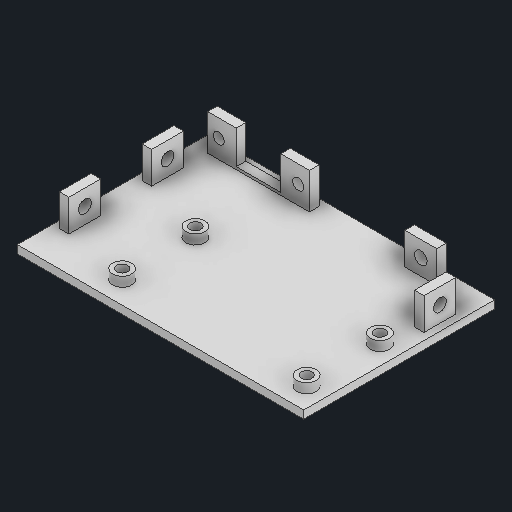
# Autodesk Inventor part: base_plate_compact
Saved by Autodesk Inventor 2027.1 (Build 311270010, 270A)
## iProperties
Created: 2026-10-29
Part Number: base_plate_compact
Material: Generic
Document SubType Name: Modeling
Designer: alexg
Density: 1 g/cm^3
Appearance: Default
Author: alexg
Autodesk Inventor part; units mm, degrees
ref_plane "Work Plane1" through (0, -31.66, 0) normal (0, 1, 0) x (-1, 0, 0)
sketch "Plate sketch" plane through (0, -31.66, 0) normal (0, 1, 0) x (-1, 0, 0)
  line L0 (45, -30) -> (-45, -30)
  line L1 (-45, -30) -> (-45, 30)
  line L2 (-45, 30) -> (45, 30)
  line L3 (45, 30) -> (45, -30)
  constraints: 8 end point, 2 parallel, 1 horizontal, 1 perpendicular
extrude "Plate" add sketch "Plate sketch" against normal blind 2.5
ref_plane "Work Plane2" through (0, -31.66, 0) normal (0, 1, 0) x (-1, 0, 0)
sketch "Pi standoffs sketch" plane through (0, -31.66, 0) normal (0, 1, 0) x (-1, 0, 0)
  circle A0 centre (-38.97, 0.03) radius 3
  circle A1 centre (19.03, 0.03) radius 3
  circle A2 centre (-38.97, 23.03) radius 3
  circle A3 centre (19.03, 23.03) radius 3
  constraints: 4 centre point
extrude "Pi standoffs" add sketch "Pi standoffs sketch" along normal blind 3
ref_plane "Work Plane3" through (0, -28.66, 0) normal (0, 1, 0) x (-1, 0, 0)
sketch "M2.5 insert holes (Pi) sketch" plane through (0, -28.66, 0) normal (0, 1, 0) x (-1, 0, 0)
  circle A0 centre (-38.97, 0.03) radius 1.75
  circle A1 centre (19.03, 0.03) radius 1.75
  circle A2 centre (-38.97, 23.03) radius 1.75
  circle A3 centre (19.03, 23.03) radius 1.75
  constraints: 4 centre point
extrude "M2.5 insert holes (Pi)" cut sketch "M2.5 insert holes (Pi) sketch" against normal blind 5
ref_plane "Work Plane4" through (0, -31.66, 0) normal (0, 1, 0) x (-1, 0, 0)
sketch "Screw tabs sketch" plane through (0, -31.66, 0) normal (0, 1, 0) x (-1, 0, 0)
  line L0 (42.8, -17) -> (39.8, -17)
  line L1 (39.8, -17) -> (39.8, -7)
  line L2 (39.8, -7) -> (42.8, -7)
  line L3 (42.8, -7) -> (42.8, -17)
  line L4 (42.8, 9) -> (39.8, 9)
  line L5 (39.8, 9) -> (39.8, 19)
  line L6 (39.8, 19) -> (42.8, 19)
  line L7 (42.8, 19) -> (42.8, 9)
  line L8 (-39.8, -20) -> (-42.8, -20)
  line L9 (-42.8, -20) -> (-42.8, -10)
  line L10 (-42.8, -10) -> (-39.8, -10)
  line L11 (-39.8, -10) -> (-39.8, -20)
  line L12 (-22, -27.8) -> (-32, -27.8)
  line L13 (-32, -27.8) -> (-32, -24.8)
  line L14 (-32, -24.8) -> (-22, -24.8)
  line L15 (-22, -24.8) -> (-22, -27.8)
  constraints: 32 end point, 8 parallel, 4 horizontal, 4 perpendicular
extrude "Screw tabs" add sketch "Screw tabs sketch" along normal blind 10
ref_plane "Work Plane5" through (-43.5, 0, 0) normal (1, 0, 0) x (0, 1, 0)
sketch "M3 insert holes L sketch" plane through (-43.5, 0, 0) normal (1, 0, 0) x (0, 1, 0)
  circle A0 centre (-26.66, -12) radius 2
  circle A1 centre (-26.66, 14) radius 2
  constraints: 2 centre point
extrude "M3 insert holes L" cut sketch "M3 insert holes L sketch" along normal blind 4
ref_plane "Work Plane6" through (43.5, 0, 0) normal (1, 0, 0) x (0, 1, 0)
sketch "M3 insert holes R sketch" plane through (43.5, 0, 0) normal (1, 0, 0) x (0, 1, 0)
  circle A0 centre (-26.66, -15) radius 2
  constraints: 1 centre point
extrude "M3 insert holes R" cut sketch "M3 insert holes R sketch" against normal blind 4
ref_plane "Work Plane7" through (0, 0, -28.5) normal (0, 0, 1) x (1, 0, 0)
sketch "M3 insert hole B sketch" plane through (0, 0, -28.5) normal (0, 0, 1) x (1, 0, 0)
  circle A0 centre (27, -26.66) radius 2
  constraints: 1 centre point
extrude "M3 insert hole B" cut sketch "M3 insert hole B sketch" along normal blind 4
ref_plane "Work Plane8" through (0, -31.66, 0) normal (0, 1, 0) x (-1, 0, 0)
sketch "USB socket bracket sketch" plane through (0, -31.66, 0) normal (0, 1, 0) x (-1, 0, 0)
  line L0 (40, -27.8) -> (8, -27.8)
  line L1 (8, -27.8) -> (8, -24.8)
  line L2 (8, -24.8) -> (40, -24.8)
  line L3 (40, -24.8) -> (40, -27.8)
  constraints: 8 end point, 2 parallel, 1 horizontal, 1 perpendicular
extrude "USB socket bracket" add sketch "USB socket bracket sketch" along normal blind 11.32
ref_plane "Work Plane9" through (0, 0, -27.8) normal (0, 0, 1) x (1, 0, 0)
sketch "External plug opening sketch" plane through (0, 0, -27.8) normal (0, 0, 1) x (1, 0, 0)
  line L0 (-31, -30.84) -> (-17, -30.84)
  line L1 (-17, -30.84) -> (-17, -19.84)
  line L2 (-17, -19.84) -> (-31, -19.84)
  line L3 (-31, -19.84) -> (-31, -30.84)
  constraints: 8 end point, 2 parallel, 1 horizontal, 1 perpendicular
extrude "External plug opening" cut sketch "External plug opening sketch" along normal blind 3
ref_plane "Work Plane10" through (0, 0, -24.8) normal (0, 0, 1) x (1, 0, 0)
sketch "M2.5x3 insert holes (USB) sketch" plane through (0, 0, -24.8) normal (0, 0, 1) x (1, 0, 0)
  circle A0 centre (-36.5, -25.84) radius 1.75
  circle A1 centre (-11.5, -25.84) radius 1.75
  constraints: 2 centre point
extrude "M2.5x3 insert holes (USB)" cut sketch "M2.5x3 insert holes (USB) sketch" against normal blind 3
body "Solid1"
